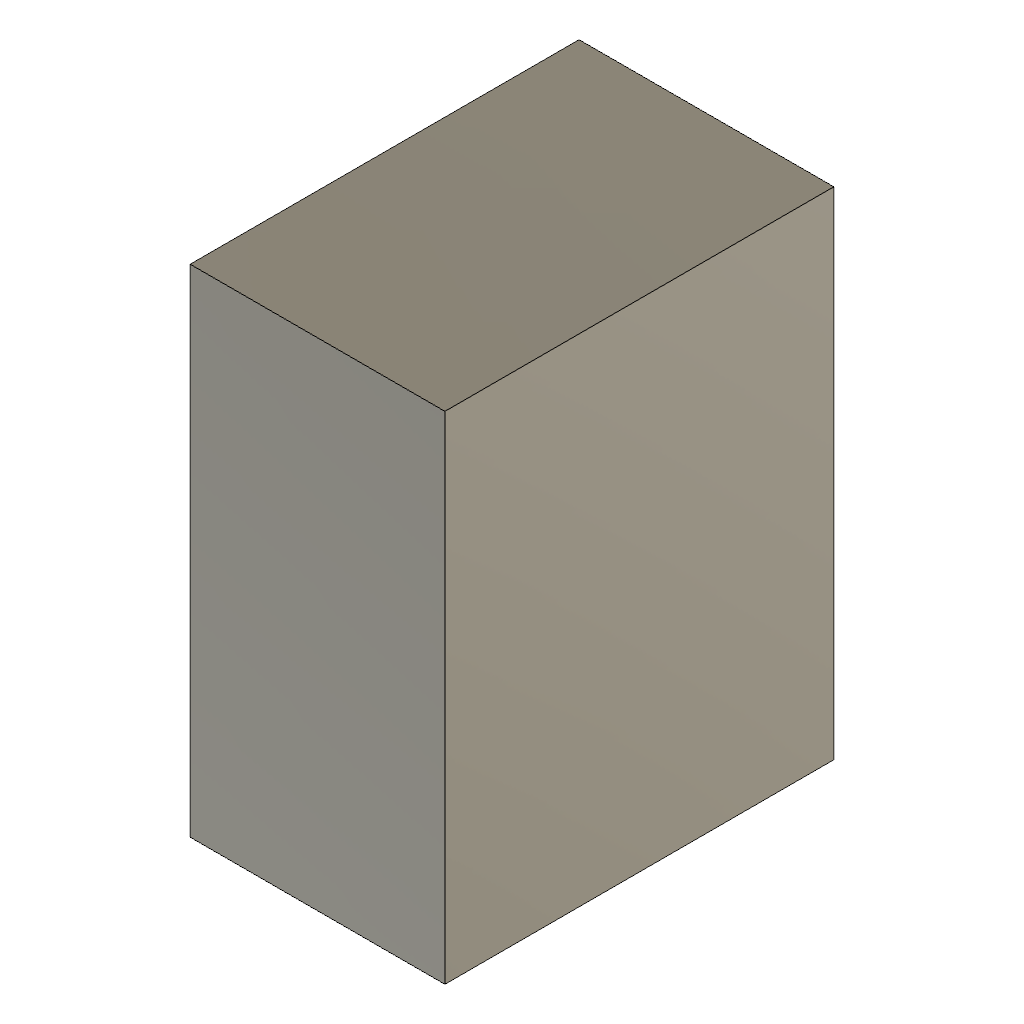
vendor_DimensionedCuboidEdited (Autodesk Fusion 360 design; units mm, degrees)
Autodesk Fusion 360 part; units mm, degrees
sketch "Constrained rectangle" plane through (0, 0, 0) normal (0, 0, 1) x (1, 0, 0)
  line L0 (0, 0) -> (19, 0)
  line L1 (19, 0) -> (19, 29)
  line L2 (19, 29) -> (0, 29)
  line L3 (0, 29) -> (0, 0)
  dimension "d6" = 19
  dimension "d7" = 29
  constraint horizontal L0
  constraint vertical L1
  constraint horizontal L2
  constraint vertical L3
  measures "d6" horizontal distance of L0.start L0.end
  measures "d7" vertical distance of L0.start L2.end
extrude "Dimension driven cuboid" add sketch "Constrained rectangle" along normal blind 37
equation "boxHeight = 37 mm"
equation "d2 = boxHeight"
equation "boxWidth = 19 mm"
equation "boxDepth = 29 mm"
equation "d6 = boxWidth"
equation "d7 = boxDepth"
